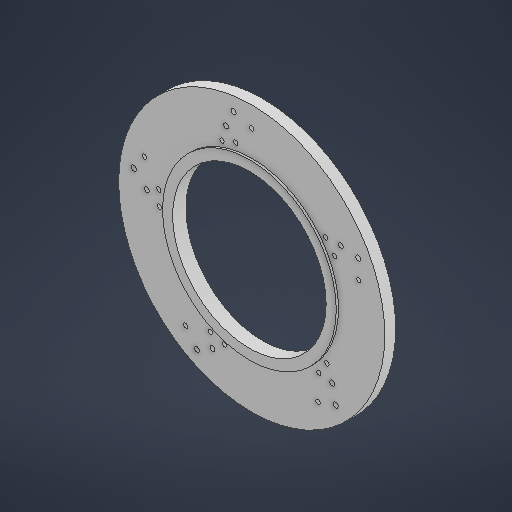
# Autodesk Inventor part: disc3 front face side
Saved by Autodesk Inventor 2027 (Build 310192060, 192F)
## iProperties
Created: 2026-07-10
Part Number: disc3 front face side
Material: Generic
Document SubType Name: Modeling
Designer: ElieH
Density: 1 g/cm^3
Appearance: Default
Author: ElieH
Autodesk Inventor part; units mm, degrees
ref_plane "YZ Plane" through (0, 0, 0) normal (1, 0, 0) x (0, 1, 0)
ref_plane "XZ Plane" through (0, 0, 0) normal (0, 1, 0) x (-1, 0, 0)
ref_plane "XY Plane" through (0, 0, 0) normal (0, 0, 1) x (1, 0, 0)
sketch "Sketch1" plane through (0, 0, 0) normal (0, 0, 1) x (1, 0, 0)
  circle A0 centre (-0.0502, -0.0753) radius 94.6473
  circle A1 centre (-0.0502, -0.0753) radius 145.0086
  line L0 (124.5437, 65.4692) -> (124.4517, 65.3073)
  arc A2 (124.5437, 65.4692) -> (124.2751, 66.4321) centre (123.9314, 65.8173) ccw
  arc A3 (123.4956, 65.0406) -> (124.4517, 65.3073) centre (123.8393, 65.6554) ccw
  circle A4 centre (-101.2189, 14.5005) radius 2.3772
  circle A5 centre (-128.5365, 20.8961) radius 2.8174
  circle A6 centre (-116.8042, 37.6521) radius 2.3772
  circle A7 centre (-100.5153, -1.427) radius 2.3772
  circle A8 centre (-114.4271, 7.8371) radius 2.7112
  circle A9 centre (-0.0502, -0.0753) radius 83.6422
  circle A10 centre (-59.6996, -115.7925) radius 2.8174
  circle A11 centre (-42.9197, -106.4091) radius 2.7112
  circle A12 centre (-29.8101, -96.0409) radius 2.3772
  circle A13 centre (-45.1755, -91.7883) radius 2.3772
  circle A14 centre (-72.0101, -99.4566) radius 2.3772
  circle A15 centre (91.5707, -92.5638) radius 2.8174
  circle A16 centre (87.8318, -73.7056) radius 2.7112
  circle A17 centre (82.0223, -58.0336) radius 2.3772
  circle A18 centre (73.2296, -71.3328) radius 2.3772
  circle A19 centre (72.2302, -99.2237) radius 2.3772
  circle A20 centre (116.2241, 58.4809) radius 2.8174
  circle A21 centre (97.1334, 60.7525) radius 2.7112
  circle A22 centre (80.4333, 60.0701) radius 2.3772
  circle A23 centre (90.3645, 47.5981) radius 2.3772
  circle A24 centre (116.5814, 38.0289) radius 2.3772
  circle A25 centre (-19.8097, 128.603) radius 2.8174
  circle A26 centre (-27.8694, 111.1487) radius 2.7112
  circle A27 centre (-32.3811, 95.055) radius 2.3772
  circle A28 centre (-17.4506, 100.6461) radius 2.3772
  circle A29 centre (-0.2483, 122.6228) radius 2.3772
  point P0 (0, 0)
  point P1 (0, -0.1004)
  dimension "d2" = 167.2844
  dimension "d3" = 290.0172
  dimension "d4" = 360
  constraints: 30 centre point, 4 point on circle, 2 end point, 1 coincident, 51 other
  measures "d2" diameter of A9
  measures "d3" diameter of A1
extrude "Extrusion1" add sketch "Sketch1" along normal blind 11.875 contours A1
extrude "Extrusion2" add sketch "Sketch1" along normal blind 14.375 contours A0
body "Solid1"
